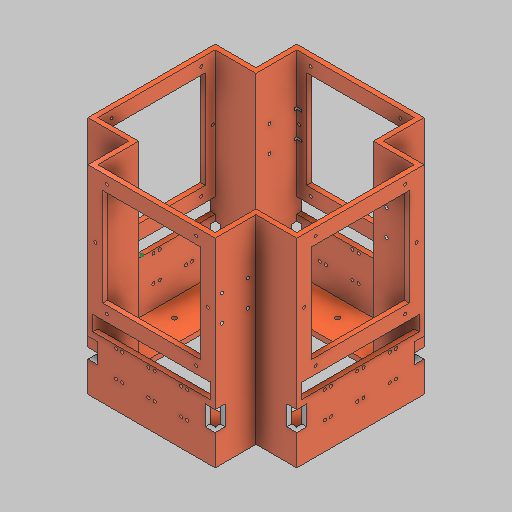
# Autodesk Inventor part: Armadura Interna
Saved by Autodesk Inventor 2027 (Build 310192000, 192)
## iProperties
Created: 2026-11-23
Part Number: Armadura Interna
Material: Genérico
Document SubType Name: Modeling
Designer: Alexander
Density: 1 g/cm^3
Appearance: Valor por defecto
Author: Alexander
Autodesk Inventor part; units mm, degrees
ref_plane "YZ Plane" through (0, 0, 0) normal (1, 0, 0) x (0, 1, 0)
ref_plane "XZ Plane" through (0, 0, 0) normal (0, 1, 0) x (-1, 0, 0)
ref_plane "XY Plane" through (0, 0, 0) normal (0, 0, 1) x (1, 0, 0)
sketch "Boceto1" plane through (0, 0, 0) normal (0, 0, 1) x (1, 0, 0)
  line L0 (-35.2785, 43.9297) -> (54.7215, 43.9297)
  line L1 (54.7215, 43.9297) -> (54.7215, -69.0703)
  line L2 (54.7215, -69.0703) -> (-35.2785, -69.0703)
  line L3 (-35.2785, -69.0703) -> (-35.2785, 43.9297)
  circle A0 centre (-35.2785, 43.9297) radius 1.5
  circle A1 centre (54.7215, 43.9297) radius 1.5
  circle A2 centre (54.7215, -69.0703) radius 1.5
  circle A3 centre (-35.2785, -69.0703) radius 1.5
  line L4 (-54.2785, 51.4297) -> (73.7215, 51.4297)
  line L5 (73.7215, 51.4297) -> (73.7215, -76.5703)
  line L6 (73.7215, -76.5703) -> (-54.2785, -76.5703)
  line L7 (-54.2785, -76.5703) -> (-54.2785, 51.4297)
  line L8 (-54.2785, -12.5703) -> (73.7215, -12.5703)
  circle A4 centre (-46.7785, -12.5703) radius 1.5
  circle A5 centre (66.2215, -12.5703) radius 1.5
  line L9 (-39.2785, 36.4297) -> (58.7215, 36.4297)
  line L10 (58.7215, 36.4297) -> (58.7215, -61.5703)
  line L11 (58.7215, -61.5703) -> (-39.2785, -61.5703)
  line L12 (-39.2785, -61.5703) -> (-39.2785, 36.4297)
  line L13 (-54.2785, 51.4297) -> (73.7215, 51.4297)
  line L14 (73.7215, 51.4297) -> (73.7215, -148.5703)
  line L15 (73.7215, -148.5703) -> (-54.2785, -148.5703)
  line L16 (-54.2785, -148.5703) -> (-54.2785, 51.4297)
  line L17 (-39.2785, -61.5703) -> (-54.2785, -61.5703)
  line L18 (-54.2785, -61.5703) -> (-54.2785, -148.5703)
  line L19 (-54.2785, -148.5703) -> (-39.2785, -148.5703)
  line L20 (-39.2785, -148.5703) -> (-39.2785, -61.5703)
  line L21 (58.7215, -61.5703) -> (73.7215, -61.5703)
  line L22 (73.7215, -61.5703) -> (73.7215, -148.5703)
  line L23 (73.7215, -148.5703) -> (58.7215, -148.5703)
  line L24 (58.7215, -148.5703) -> (58.7215, -61.5703)
  line L25 (-54.2785, -148.5703) -> (73.7215, -148.5703)
  line L26 (73.7215, -148.5703) -> (73.7215, -143.5703)
  line L27 (73.7215, -143.5703) -> (-54.2785, -143.5703)
  line L28 (-54.2785, -143.5703) -> (-54.2785, -148.5703)
  point P0 (0, 0)
  point P1 (-39.2785, -61.5703)
  point P2 (-39.2785, -143.5703)
  point P3 (-39.2785, -76.5703)
  point P4 (58.7215, -76.5703)
  point P5 (58.7215, -143.5703)
  point P6 (-54.2785, -76.5703)
  dimension "d0" = 90
  dimension "d1" = 113
  dimension "d2" = 3
  dimension "d3" = 3
  dimension "d4" = 3
  dimension "d5" = 3
  dimension "d6" = 128
  dimension "d7" = 128
  dimension "d8" = 7.5
  dimension "d9" = 19
  dimension "d10" = 3
  dimension "d11" = 3
  dimension "d12" = 7.5
  dimension "d13" = 7.5
  dimension "d14" = 15
  dimension "d15" = 15
  dimension "d16" = 15
  dimension "d17" = 15
  dimension "d18" = 15
  dimension "d19" = 15
  dimension "d20" = 15
  dimension "d21" = 15
  dimension "d22" = 200
  dimension "d23" = 5
  constraints: 58 end point, 14 parallel, 7 horizontal, 7 perpendicular, 6 centre point, 4 coincident, 3 point on line, 2 midpoint
  measures "d0" distance of L0.start L0.end
  measures "d1" distance of L2.end L0.start
  measures "d2" diameter of A0
  measures "d3" diameter of A1
  measures "d4" diameter of A2
  measures "d5" diameter of A3
  measures "d6" distance of L4.start L4.end
  measures "d7" distance of L6.end L4.start
  measures "d8" distance from line of L4 A0.centre
  measures "d9" distance from line of L7 A0.centre
  measures "d10" diameter of A4
  measures "d11" diameter of A5
  measures "d12" distance from line of L5 A5.centre
  measures "d13" distance from line of L7 A4.centre
  measures "d14" distance from line of L5 L10.end
  measures "d15" distance from line of L10.end L6
  measures "d16" distance from line of point (58.722, 36.43) L4
  measures "d17" distance from line of point (58.722, 36.43) L5
  measures "d18" distance from line of L7 L9.start
  measures "d19" distance from line of L9.start L4
  measures "d20" distance from line of L7 point (-39.278, -61.57)
  measures "d21" distance from line of point (-39.278, -61.57) L6
  measures "d22" distance between parallel lines of L15 L13
  measures "d23" distance between parallel lines of L27 L15
extrude "Extrusión1" add sketch "Boceto1" along normal blind 5 contours A0 L3 L9 L12 L8 A4 L7 L4 L5 A5 L10 L1 A1 L0 | L0 A1 L1 L9 L3 A0 | L11 L1 A2 L2 A3 L3 | L3 A3 L2 A2 L1 L11 L24 L6 L20 | L12 L17 L7 L8 A4 | L20 L6 L7 L17 | L8 A5 L5 L21 L10 | L21 L5 L6 L24 | L20 L27 L16 L6 | L6 L14 L27 L24 | L27 L24 L15 L20 | L20 L15 L16 L27 | L27 L14 L15 L24
extrude "Extrusión2" add sketch "Boceto1" along normal blind 40 contours L27 L24 L15 L20
extrude "Extrusión3" add sketch "Boceto1" along normal blind 41 contours L27 L24 L15 L20 | L20 L15 L16 L27 | L27 L14 L15 L24
sketch "Boceto2" plane through (-54.2785, 51.4297, 0) normal (0, 1, 0) x (1, 0, 0)
  line L0 (0, 0) -> (0, -41) projected
  line L1 (0, 0) -> (128, 0)
  line L2 (128, 0) -> (128, -210)
  line L3 (128, -210) -> (0, -210)
  line L4 (0, -210) -> (0, 0)
  line L5 (0, -169) -> (128, -169)
  line L6 (128, -169) -> (128, -41)
  line L7 (128, -41) -> (0, -41)
  line L8 (0, -41) -> (0, -169)
  line L9 (169, -41) -> (-41, -41)
  line L10 (-41, -41) -> (-41, -169)
  line L11 (-41, -169) -> (169, -169)
  line L12 (169, -169) -> (169, -41)
  line L13 (0, 0) -> (5, 0)
  line L14 (5, 0) -> (5, -210)
  line L15 (5, -210) -> (0, -210)
  line L16 (0, -210) -> (0, 0)
  line L17 (128, 0) -> (123, 0)
  line L18 (123, 0) -> (123, -210)
  line L19 (123, -210) -> (128, -210)
  line L20 (128, -210) -> (128, 0)
  line L21 (-41, -41) -> (169, -41)
  line L22 (169, -41) -> (169, -46)
  line L23 (169, -46) -> (-41, -46)
  line L24 (-41, -46) -> (-41, -41)
  line L25 (169, -169) -> (-41, -169)
  line L26 (-41, -169) -> (-41, -164)
  line L27 (-41, -164) -> (169, -164)
  line L28 (169, -164) -> (169, -169)
  line L29 (169, -41) -> (164, -41)
  line L30 (164, -41) -> (164, -169)
  line L31 (164, -169) -> (169, -169)
  line L32 (169, -169) -> (169, -41)
  line L33 (-41, -41) -> (-36, -41)
  line L34 (-36, -41) -> (-36, -169)
  line L35 (-36, -169) -> (-41, -169)
  line L36 (-41, -169) -> (-41, -41)
  line L37 (0, -210) -> (128, -210)
  line L38 (128, -210) -> (128, -205)
  line L39 (128, -205) -> (0, -205)
  line L40 (0, -205) -> (0, -210)
  point P0 (54.2785, 0)
  point P1 (164, -164)
  point P2 (123, -164)
  point P3 (123, -205)
  point P4 (5, -205)
  point P5 (5, -164)
  point P6 (-36, -164)
  point P7 (-36, -46)
  point P8 (5, -46)
  point P9 (0, -169)
  point P10 (123, -46)
  point P11 (164, -46)
  dimension "d34" = 128
  dimension "d35" = 210
  dimension "d36" = 128
  dimension "d37" = 41
  dimension "d38" = 41
  dimension "d39" = 41
  dimension "d40" = 5
  dimension "d41" = 5
  dimension "d42" = 5
  dimension "d43" = 5
  dimension "d44" = 5
  dimension "d45" = 5
  dimension "d46" = 5
  constraints: 80 end point, 20 parallel, 10 horizontal, 10 perpendicular, 10 point on line
  measures "d34" distance of L2.end L3.end
  measures "d35" distance of L1.end L2.end
  measures "d36" distance of L6.end L5.end
  measures "d37" distance between parallel lines of L5 L3
  measures "d38" distance between parallel lines of L4 L10
  measures "d39" distance between parallel lines of L12 L2
  measures "d40" distance of L14.end L15.end
  measures "d41" distance of L19.end L18.end
  measures "d42" distance of L21.end L22.end
  measures "d43" distance of L25.end L26.end
  measures "d44" distance of L31.end L30.end
  measures "d45" distance of L34.end L35.end
  measures "d46" distance of L38.end L37.end
extrude "Extrusión4" add sketch "Boceto2" against normal blind 200 contours L1 L14 L7 L0 | L7 L14 L23 L4 | L4 L23 L34 L9 | L34 L23 L10 L9 | L1 L2 L7 L18 | L27 L14 L5 L4 | L4 L11 L34 L27 | L34 L27 L10 L23 | L7 L2 L23 L18 | L5 L14 L39 L4 | L34 L11 L10 L27 | L9 L30 L23 L2 | L39 L14 L3 L4 | L27 L2 L5 L18 | L9 L12 L23 L30 | L39 L18 L3 L14 | L5 L2 L39 L18 | L27 L30 L11 L2 | L23 L12 L27 L30 | L39 L2 L3 L18 | L27 L12 L11 L30
sketch "Boceto4" plane through (68.7215, 51.4297, 205) normal (0, 0, -1) x (-1, 0, 0)
  line L0 (10, -15) -> (10, -113) projected
  line L1 (10, -15) -> (108, -15)
  line L2 (108, -15) -> (108, -113)
  line L3 (108, -113) -> (10, -113)
  line L4 (10, -113) -> (10, -15)
  line L5 (108, -128) -> (10, -128) projected
  line L6 (10, -195) -> (108, -195) projected
  line L7 (10, -128) -> (108, -128)
  line L8 (108, -128) -> (108, -195)
  line L9 (108, -195) -> (10, -195)
  line L10 (10, -195) -> (10, -128)
  circle A0 centre (14, -120.5) radius 1.5 projected
  circle A1 centre (14, -120.5) radius 1.5
  circle A2 centre (104, -120.5) radius 1.5 projected
  circle A3 centre (104, -120.5) radius 1.5
  circle A4 centre (115.5, -64) radius 1.5 projected
  circle A5 centre (115.5, -64) radius 1.5
  circle A6 centre (104, -7.5) radius 1.5 projected
  circle A7 centre (104, -7.5) radius 1.5
  circle A8 centre (14, -7.5) radius 1.5 projected
  circle A9 centre (14, -7.5) radius 1.5
  circle A10 centre (2.5, -64) radius 1.5 projected
  circle A11 centre (2.5, -64) radius 1.5
  point P0 (68.7215, -51.4297)
  point P1 (10, -113)
  constraints: 16 end point, 6 centre point, 6 coincident, 4 parallel, 2 horizontal, 2 perpendicular
extrude "Extrusión5" cut sketch "Boceto4" against normal blind 200
sketch "Boceto5" plane through (-95.2785, 51.4297, 41) normal (-1, 0, 0) x (0, 0, 1)
  line L0 (15, -15) -> (113, -15)
  line L1 (113, -15) -> (113, -113)
  line L2 (113, -113) -> (15, -113)
  line L3 (15, -113) -> (15, -15)
  line L4 (0, 0) -> (128, 0) projected
  line L5 (0, 0) -> (0, -200) projected
  line L6 (15, -128) -> (113, -128)
  line L7 (113, -128) -> (113, -195)
  line L8 (113, -195) -> (15, -195)
  line L9 (15, -195) -> (15, -128)
  line L10 (128, -200) -> (0, -200) projected
  point P0 (-41, -51.4297)
  dimension "d51" = 98
  dimension "d52" = 98
  dimension "d53" = 15
  dimension "d54" = 15
  dimension "d55" = 5
  dimension "d56" = 15
  constraints: 16 end point, 4 parallel, 2 horizontal, 2 perpendicular
  measures "d51" distance of L1.end L2.end
  measures "d52" distance of L0.end L1.end
  measures "d53" distance between parallel lines of L4 L0
  measures "d54" distance between parallel lines of L5 L3
  measures "d55" distance between parallel lines of L10 L8
  measures "d56" distance between parallel lines of L6 L2
extrude "Extrusión6" cut sketch "Boceto5" against normal blind 243.75
sketch "Boceto6" plane through (-95.2785, 51.4297, 41) normal (-1, 0, 0) x (0, 0, 1)
  circle A0 centre (19, -7.5) radius 1.5
  circle A1 centre (109, -7.5) radius 1.5
  circle A2 centre (19, -120.5) radius 1.5
  circle A3 centre (109, -120.5) radius 1.5
  line L0 (0, 0) -> (128, 0) projected
  line L1 (113, -113) -> (15, -113) projected
  line L2 (128, 0) -> (128, -200) projected
  line L3 (15, -113) -> (15, -15) projected
  line L4 (15, -64) -> (0, -64)
  line L5 (0, 0) -> (0, -200) projected
  line L6 (113, -15) -> (113, -113) projected
  line L7 (113, -64) -> (128, -64)
  circle A4 centre (7.5, -64) radius 1.5
  circle A5 centre (120.5, -64) radius 1.5
  point P0 (-41, -51.4297)
  dimension "d59" = 3
  dimension "d60" = 3
  dimension "d61" = 90
  dimension "d62" = 3
  dimension "d63" = 3
  dimension "d64" = 7.5
  dimension "d65" = 7.5
  dimension "d67" = 7.5
  dimension "d69" = 7.5
  dimension "d70" = 19
  dimension "d71" = 19
  dimension "d72" = 90
  dimension "d73" = 3
  dimension "d74" = 3
  constraints: 6 centre point, 4 end point, 4 midpoint, 3 point on line, 1 horizontal
  measures "d59" diameter of A0
  measures "d60" diameter of A1
  measures "d61" distance of A0.centre A1.centre
  measures "d62" diameter of A2
  measures "d63" diameter of A3
  measures "d64" distance from line of L0 A0.centre
  measures "d65" distance from line of A1.centre L0
  measures "d67" distance from line of L1 A2.centre
  measures "d69" distance from line of L1 A3.centre
  measures "d70" distance from line of L2 A1.centre
  measures "d71" distance from line of L2 A3.centre
  measures "d72" distance of A2.centre A3.centre
  measures "d73" diameter of A4
  measures "d74" diameter of A5
extrude "Extrusión7" cut sketch "Boceto6" against normal blind 243.75 contours A0 | A1 | A2 | A3 | A4 L4 | L4 A4 | A5 L7 | L7 A5
sketch "Boceto7" plane through (-54.2785, -148.5703, 0) normal (0, -1, 0) x (1, 0, 0)
  line L0 (123, 164) -> (123, 205) projected
  line L1 (169, 41) -> (128, 41) projected
  line L2 (123, 164) -> (169, 164)
  line L3 (169, 164) -> (169, 41)
  line L4 (169, 41) -> (123, 41)
  line L5 (123, 41) -> (123, 164)
  line L6 (0, 210) -> (0, 169) projected
  line L7 (123, 164) -> (0, 164)
  line L8 (0, 164) -> (0, 210)
  line L9 (0, 210) -> (123, 210)
  line L10 (123, 210) -> (123, 164)
  line L11 (-41, 169) -> (-41, 41) projected
  line L12 (5, 164) -> (5, 205) projected
  line L13 (-41, 41) -> (5, 41)
  line L14 (5, 41) -> (5, 164)
  line L15 (5, 164) -> (-41, 164)
  line L16 (-41, 164) -> (-41, 41)
  line L17 (-36, 46) -> (5, 46) projected
  line L18 (123, 41) -> (-36, 41)
  line L19 (-36, 41) -> (-36, 46)
  line L20 (-36, 46) -> (123, 46)
  line L21 (123, 46) -> (123, 41)
  point P0 (54.2785, 0)
  point P1 (0, 164)
  point P2 (-36, 41)
  constraints: 32 end point, 8 parallel, 4 horizontal, 4 perpendicular
extrude "Extrusión8" add sketch "Boceto7" against normal blind 5 contours L7 L8 L6 L9 L10 L0 | L2 L3 L1 L4 L5 | L5 L18 L14 L20 | L14 L17 L19 L13 L11 L15 L7
sketch "Boceto8" plane through (109.7215, -143.5703, 56) normal (0, 1, 0) x (1, 0, 0)
  line L0 (5, 0) -> (5, -98) projected
  line L1 (5, -49) -> (-205, -49)
  line L2 (-205, 0) -> (-205, -98) projected
  line L3 (-51, -154) -> (-149, -154) projected
  line L4 (-100, -154) -> (-100, 56)
  line L5 (-51, 56) -> (-149, 56) projected
  line L6 (-41, -108) -> (-41, 10) projected
  line L7 (-41, -49) -> (5, -49)
  line L8 (-41, -108) -> (-159, -108) projected
  line L9 (-100, -108) -> (-100, -154)
  line L10 (-149, -149) -> (-51, -149) projected
  line L11 (-205, -49) -> (-159, -49)
  line L12 (-159, -108) -> (-159, 10) projected
  line L13 (-100, 56) -> (-100, 10)
  line L14 (-41, 10) -> (-159, 10) projected
  circle A0 centre (-100, -131) radius 2.5
  circle A1 centre (-18, -49) radius 2.5
  circle A2 centre (-100, 33) radius 2.5
  circle A3 centre (-182, -49) radius 2.5
  point P0 (-109.7215, 56)
  dimension "d79" = 5
  dimension "d80" = 5
  dimension "d81" = 5
  dimension "d82" = 5
  constraints: 12 end point, 12 midpoint, 4 centre point, 2 perpendicular
  measures "d79" diameter of A0
  measures "d80" diameter of A1
  measures "d81" diameter of A2
  measures "d82" diameter of A3
extrude "Extrusión9" cut sketch "Boceto8" against normal blind 5 contours A3 L1 | L1 A3 | A2 L4 | L4 A2 | A1 L1 | L1 A1 | A0 L4 | L4 A0
sketch "Boceto9" plane through (-54.2785, 51.4297, 210) normal (0, 0, 1) x (1, 0, 0)
  line L0 (5, 0) -> (5, -195) projected
  line L1 (113, -195) -> (123, -195) projected
  line L2 (5, -127.8283) -> (123, -127.8283)
  line L3 (123, -127.8283) -> (123, -195)
  line L4 (123, -195) -> (5, -195)
  line L5 (5, -195) -> (5, -127.8283)
  point P0 (54.2785, -51.4297)
  constraints: 8 end point, 2 parallel, 1 horizontal, 1 perpendicular, 1 point on line
extrude "Extrusión10" cut sketch "Boceto9" against normal blind 306.75
sketch "Boceto10" plane through (114.7215, 51.4297, 169) normal (1, 0, 0) x (0, 0, -1)
  line L0 (5, -195) -> (123, -195) projected
  line L1 (5, 0) -> (5, -195) projected
  line L2 (123, -195) -> (5, -195)
  line L3 (5, -195) -> (5, -127.9827)
  line L4 (5, -127.9827) -> (123, -127.9827)
  line L5 (123, -127.9827) -> (123, -195)
  point P0 (169, -51.4297)
  constraints: 8 end point, 2 parallel, 1 horizontal, 1 perpendicular, 1 point on line
extrude "Extrusión11" cut sketch "Boceto10" against normal blind 306.75
sketch "Boceto11" plane through (114.7215, 51.4297, 169) normal (1, 0, 0) x (0, 0, -1)
  line L0 (-2.5, -143) -> (130.5, -143)
  line L1 (130.5, -143) -> (130.5, -176)
  line L2 (130.5, -176) -> (-2.5, -176)
  line L3 (-2.5, -176) -> (-2.5, -143)
  line L4 (128, -200) -> (0, -200) projected
  line L5 (64, -200) -> (64, -113)
  line L6 (15, -113) -> (113, -113) projected
  line L7 (1.7375, -146) -> (28.2375, -146)
  line L8 (28.2375, -146) -> (28.2375, -172.5)
  line L9 (28.2375, -172.5) -> (1.7375, -172.5)
  line L10 (1.7375, -172.5) -> (1.7375, -146)
  line L11 (28.2375, -146) -> (34.4125, -146)
  line L12 (34.4125, -146) -> (34.4125, -172.5)
  line L13 (34.4125, -172.5) -> (28.2375, -172.5)
  line L14 (28.2375, -172.5) -> (28.2375, -146)
  line L15 (34.4125, -146) -> (60.9125, -146)
  line L16 (60.9125, -146) -> (60.9125, -172.5)
  line L17 (60.9125, -172.5) -> (34.4125, -172.5)
  line L18 (34.4125, -172.5) -> (34.4125, -146)
  line L19 (60.9125, -146) -> (67.0875, -146)
  line L20 (67.0875, -146) -> (67.0875, -172.5)
  line L21 (67.0875, -172.5) -> (60.9125, -172.5)
  line L22 (60.9125, -172.5) -> (60.9125, -146)
  line L23 (67.0875, -146) -> (93.5875, -146)
  line L24 (93.5875, -146) -> (93.5875, -172.5)
  line L25 (93.5875, -172.5) -> (67.0875, -172.5)
  line L26 (67.0875, -172.5) -> (67.0875, -146)
  line L27 (93.5875, -172.5) -> (99.7625, -172.5)
  line L28 (99.7625, -172.5) -> (99.7625, -146)
  line L29 (99.7625, -146) -> (93.5875, -146)
  line L30 (93.5875, -146) -> (93.5875, -172.5)
  line L31 (99.7625, -146) -> (126.2625, -146)
  line L32 (126.2625, -146) -> (126.2625, -172.5)
  line L33 (126.2625, -172.5) -> (99.7625, -172.5)
  line L34 (99.7625, -172.5) -> (99.7625, -146)
  circle A0 centre (1.7375, -146) radius 1.6
  circle A1 centre (28.2375, -146) radius 1.6
  circle A2 centre (60.9125, -146) radius 1.6
  circle A3 centre (67.0875, -146) radius 1.6
  circle A4 centre (34.4125, -146) radius 1.6
  circle A5 centre (93.5875, -146) radius 1.6
  circle A6 centre (99.7625, -146) radius 1.6
  circle A7 centre (126.2625, -146) radius 1.6
  circle A8 centre (1.7375, -172.5) radius 1.6
  circle A9 centre (28.2375, -172.5) radius 1.6
  circle A10 centre (34.4125, -172.5) radius 1.6
  circle A11 centre (60.9125, -172.5) radius 1.6
  circle A12 centre (67.0875, -172.5) radius 1.6
  circle A13 centre (93.5875, -172.5) radius 1.6
  circle A14 centre (99.7625, -172.5) radius 1.6
  circle A15 centre (126.2625, -172.5) radius 1.6
  line L35 (128, -200) -> (128, 0) projected
  line L36 (0, -200) -> (128, -200)
  line L37 (128, -200) -> (128, -113)
  line L38 (128, -113) -> (0, -113)
  line L39 (0, -113) -> (0, -200)
  point P0 (169, -51.4297)
  point P1 (0, -143)
  point P2 (128, -143)
  dimension "d89" = 133
  dimension "d90" = 66.5
  dimension "d91" = 30
  dimension "d92" = 33
  dimension "d93" = 26.5
  dimension "d94" = 26.5
  dimension "d95" = 6.175
  dimension "d96" = 26.5
  dimension "d97" = 6.175
  dimension "d98" = 26.5
  dimension "d99" = 6.175
  dimension "d100" = 26.5
  dimension "d101" = 4.2375
  dimension "d102" = 3
  dimension "d103" = 4.2375
  dimension "d104" = 3.2
  dimension "d105" = 3.2
  dimension "d106" = 3.2
  dimension "d107" = 3.2
  dimension "d108" = 3.2
  dimension "d109" = 3.2
  dimension "d110" = 3.2
  dimension "d111" = 3.2
  dimension "d112" = 3.2
  dimension "d113" = 3.2
  dimension "d114" = 3.2
  dimension "d115" = 3.2
  dimension "d116" = 3.2
  dimension "d117" = 3.2
  dimension "d118" = 3.2
  dimension "d119" = 3.2
  dimension "d120" = 24
  constraints: 74 end point, 18 parallel, 16 centre point, 16 coincident, 9 horizontal, 9 perpendicular, 4 point on line, 2 midpoint
  measures "d89" distance of L1.end L2.end
  measures "d90" distance between parallel lines of L5 L1
  measures "d91" distance between parallel lines of L0 L6
  measures "d92" distance between parallel lines of L2 L0
  measures "d93" distance of L8.end L9.end
  measures "d94" distance of L7.end L8.end
  measures "d95" distance of L12.end L13.end
  measures "d96" distance of L16.end L17.end
  measures "d97" distance of L20.end L21.end
  measures "d98" distance of L24.end L25.end
  measures "d99" distance of L29.end L28.end
  measures "d100" distance of L32.end L33.end
  measures "d101" distance between parallel lines of L3 L10
  measures "d102" distance between parallel lines of L0 L7
  measures "d103" distance between parallel lines of L32 L1
  measures "d104" diameter of A0
  measures "d105" diameter of A1
  measures "d106" diameter of A2
  measures "d107" diameter of A3
  measures "d108" diameter of A4
  measures "d109" diameter of A5
  measures "d110" diameter of A6
  measures "d111" diameter of A7
  measures "d112" diameter of A8
  measures "d113" diameter of A9
  measures "d114" diameter of A10
  measures "d115" diameter of A11
  measures "d116" diameter of A12
  measures "d117" diameter of A13
  measures "d118" diameter of A14
  measures "d119" diameter of A15
  measures "d120" distance between parallel lines of L4 L2
sketch "Boceto12" plane through (-54.2785, 51.4297, 210) normal (0, 0, 1) x (1, 0, 0)
  point P0 (54.2785, -51.4297)
sketch "Boceto13" plane through (-54.2785, 51.4297, 210) normal (0, 0, 1) x (1, 0, 0)
  line L0 (-2.502, -142.9987) -> (130.498, -142.9987)
  line L1 (130.498, -142.9987) -> (130.498, -175.9987)
  line L2 (130.498, -175.9987) -> (-2.502, -175.9987)
  line L3 (-2.502, -175.9987) -> (-2.502, -142.9987)
  line L4 (127.998, -199.9987) -> (-0.002, -199.9987)
  line L5 (63.998, -199.9987) -> (63.998, -112.9987)
  line L6 (14.998, -112.9987) -> (112.998, -112.9987)
  line L7 (1.7355, -145.9987) -> (28.2355, -145.9987)
  line L8 (28.2355, -145.9987) -> (28.2355, -172.4987)
  line L9 (28.2355, -172.4987) -> (1.7355, -172.4987)
  line L10 (1.7355, -172.4987) -> (1.7355, -145.9987)
  line L11 (28.2355, -145.9987) -> (34.4105, -145.9987)
  line L12 (34.4105, -145.9987) -> (34.4105, -172.4987)
  line L13 (34.4105, -172.4987) -> (28.2355, -172.4987)
  line L14 (28.2355, -172.4987) -> (28.2355, -145.9987)
  line L15 (34.4105, -145.9987) -> (60.9105, -145.9987)
  line L16 (60.9105, -145.9987) -> (60.9105, -172.4987)
  line L17 (60.9105, -172.4987) -> (34.4105, -172.4987)
  line L18 (34.4105, -172.4987) -> (34.4105, -145.9987)
  line L19 (60.9105, -145.9987) -> (67.0855, -145.9987)
  line L20 (67.0855, -145.9987) -> (67.0855, -172.4987)
  line L21 (67.0855, -172.4987) -> (60.9105, -172.4987)
  line L22 (60.9105, -172.4987) -> (60.9105, -145.9987)
  line L23 (67.0855, -145.9987) -> (93.5855, -145.9987)
  line L24 (93.5855, -145.9987) -> (93.5855, -172.4987)
  line L25 (93.5855, -172.4987) -> (67.0855, -172.4987)
  line L26 (67.0855, -172.4987) -> (67.0855, -145.9987)
  line L27 (93.5855, -172.4987) -> (99.7605, -172.4987)
  line L28 (99.7605, -172.4987) -> (99.7605, -145.9987)
  line L29 (99.7605, -145.9987) -> (93.5855, -145.9987)
  line L30 (93.5855, -145.9987) -> (93.5855, -172.4987)
  line L31 (99.7605, -145.9987) -> (126.2605, -145.9987)
  line L32 (126.2605, -145.9987) -> (126.2605, -172.4987)
  line L33 (126.2605, -172.4987) -> (99.7605, -172.4987)
  line L34 (99.7605, -172.4987) -> (99.7605, -145.9987)
  circle A0 centre (1.7355, -145.9987) radius 1.6
  circle A1 centre (28.2355, -145.9987) radius 1.6
  circle A2 centre (60.9105, -145.9987) radius 1.6
  circle A3 centre (67.0855, -145.9987) radius 1.6
  circle A4 centre (34.4105, -145.9987) radius 1.6
  circle A5 centre (93.5855, -145.9987) radius 1.6
  circle A6 centre (99.7605, -145.9987) radius 1.6
  circle A7 centre (126.2605, -145.9987) radius 1.6
  circle A8 centre (1.7355, -172.4987) radius 1.6
  circle A9 centre (28.2355, -172.4987) radius 1.6
  circle A10 centre (34.4105, -172.4987) radius 1.6
  circle A11 centre (60.9105, -172.4987) radius 1.6
  circle A12 centre (67.0855, -172.4987) radius 1.6
  circle A13 centre (93.5855, -172.4987) radius 1.6
  circle A14 centre (99.7605, -172.4987) radius 1.6
  circle A15 centre (126.2605, -172.4987) radius 1.6
  line L35 (-0.002, -199.9987) -> (127.998, -199.9987)
  line L36 (127.998, -199.9987) -> (127.998, -112.9987)
  line L37 (127.998, -112.9987) -> (-0.002, -112.9987)
  line L38 (-0.002, -112.9987) -> (-0.002, -199.9987)
  line L39 (5, -127.8283) -> (5, -195) projected
  line L40 (169, -195) -> (123, -195) projected
  line L41 (5, -142.9987) -> (123, -142.9987)
  line L42 (123, -142.9987) -> (123, -195)
  line L43 (123, -195) -> (5, -195)
  line L44 (5, -195) -> (5, -142.9987)
  point P0 (54.2785, -51.4297)
  dimension "d121" = 133
  dimension "d122" = 66.5
  dimension "d123" = 30
  dimension "d124" = 33
  dimension "d125" = 26.5
  dimension "d126" = 26.5
  dimension "d127" = 6.175
  dimension "d128" = 26.5
  dimension "d129" = 6.175
  dimension "d130" = 26.5
  dimension "d131" = 6.175
  dimension "d132" = 26.5
  dimension "d133" = 4.2375
  dimension "d134" = 3
  dimension "d135" = 4.2375
  dimension "d136" = 3.2
  dimension "d137" = 3.2
  dimension "d138" = 3.2
  dimension "d139" = 3.2
  dimension "d140" = 3.2
  dimension "d141" = 3.2
  dimension "d142" = 3.2
  dimension "d143" = 3.2
  dimension "d144" = 3.2
  dimension "d145" = 3.2
  dimension "d146" = 3.2
  dimension "d147" = 3.2
  dimension "d148" = 3.2
  dimension "d149" = 3.2
  dimension "d150" = 3.2
  dimension "d151" = 3.2
  dimension "d152" = 24
  constraints: 86 end point, 20 parallel, 16 centre point, 16 coincident, 10 horizontal, 10 perpendicular, 5 point on line, 2 midpoint
  measures "d121" distance of L1.end L2.end
  measures "d122" distance between parallel lines of L5 L1
  measures "d123" distance between parallel lines of L0 L6
  measures "d124" distance between parallel lines of L2 L0
  measures "d125" distance of L9.start L9.end
  measures "d126" distance of L11.start L9.start
  measures "d127" distance of L13.start L13.end
  measures "d128" distance of L16.end L17.end
  measures "d129" distance of L20.end L21.end
  measures "d130" distance of L25.start L25.end
  measures "d131" distance of L30.start L29.start
  measures "d132" distance of L33.start L33.end
  measures "d133" distance between parallel lines of L3 L10
  measures "d134" distance between parallel lines of L0 L7
  measures "d135" distance between parallel lines of L32 L1
  measures "d136" diameter of A0
  measures "d137" diameter of A1
  measures "d138" diameter of A2
  measures "d139" diameter of A3
  measures "d140" diameter of A4
  measures "d141" diameter of A5
  measures "d142" diameter of A6
  measures "d143" diameter of A7
  measures "d144" diameter of A8
  measures "d145" diameter of A9
  measures "d146" diameter of A10
  measures "d147" diameter of A11
  measures "d148" diameter of A12
  measures "d149" diameter of A13
  measures "d150" diameter of A14
  measures "d151" diameter of A15
  measures "d152" distance between parallel lines of L4 L2
extrude "Extrusión12" add sketch "Boceto13" against normal blind 5 contours L0 L5 L19 A2 L15 A4 L11 A1 L7 L39 | L0 L42 L31 A6 L29 A5 L23 A3 L19 L5 | L7 A1 L8 A9 L9 L39 | L39 L9 A9 L13 A10 L17 A11 L21 L5 L2 | L2 L5 L43 L39 | L19 A3 L20 A12 L21 L5 | L5 L21 A11 L16 A2 L19 | L5 L21 A12 L25 A13 L27 A14 L33 L42 L2 | L2 L42 L43 L5 | L42 L33 A14 L28 A6 L31 | L11 A4 L12 A10 L13 A9 L8 A1 | A2 L16 A11 L17 A10 L12 A4 L15 | L23 A5 L24 A13 L25 A12 L20 A3 | A6 L28 A14 L27 A13 L24 A5 L29
extrude "Extrusión13" add sketch "Boceto11" against normal blind 5 contours L0 L5 L19 A2 L15 A4 L11 A1 L7 A0 L10 A8 L9 A9 L13 A10 L17 A11 L21 L2 L39 | L0 L35 L2 L5 L21 A12 L25 A13 L27 A14 L33 A15 L32 A7 L31 A6 L29 A5 L23 A3 L19 | L2 L5 L4 L39 | L19 A3 L20 A12 L21 L5 | L5 L21 A11 L16 A2 L19 | L2 L35 L4 L5 | A2 L16 A11 L17 A10 L12 A4 L15 | L23 A5 L24 A13 L25 A12 L20 A3 | A4 L12 A10 L13 A9 L8 A1 L11 | L29 A6 L28 A14 L27 A13 L24 A5 | A1 L8 A9 L9 A8 L10 A0 L7 | L31 A7 L32 A15 L33 A14 L28 A6
sketch "Boceto14" plane through (0, 0, 0) normal (0, 0, -1) x (-1, 0, 0)
  line L0 (49.2785, -91.569) -> (-68.7215, -91.569) projected
  line L1 (49.2785, 51.4297) -> (49.2785, -143.5703) projected
  line L2 (-68.7215, -91.569) -> (49.2785, -91.569)
  line L3 (49.2785, -91.569) -> (49.2785, -143.5703)
  line L4 (49.2785, -143.5703) -> (-68.7215, -143.5703)
  line L5 (-68.7215, -143.5703) -> (-68.7215, -91.569)
  circle A0 centre (-45.482, -94.569) radius 1.6 projected
  circle A1 centre (-45.482, -94.569) radius 1.6
  circle A2 centre (-39.307, -94.569) radius 1.6 projected
  circle A3 centre (-39.307, -94.569) radius 1.6
  circle A4 centre (-45.482, -121.069) radius 1.6 projected
  circle A5 centre (-45.482, -121.069) radius 1.6
  circle A6 centre (-39.307, -121.069) radius 1.6 projected
  circle A7 centre (-39.307, -121.069) radius 1.6
  circle A8 centre (-12.807, -94.569) radius 1.6 projected
  circle A9 centre (-12.807, -94.569) radius 1.6
  circle A10 centre (-12.807, -121.069) radius 1.6 projected
  circle A11 centre (-12.807, -121.069) radius 1.6
  circle A12 centre (-6.632, -94.569) radius 1.6 projected
  circle A13 centre (-6.632, -94.569) radius 1.6
  circle A14 centre (19.868, -94.569) radius 1.6 projected
  circle A15 centre (19.868, -94.569) radius 1.6
  circle A16 centre (26.043, -94.569) radius 1.6 projected
  circle A17 centre (26.043, -94.569) radius 1.6
  circle A18 centre (19.868, -121.069) radius 1.6 projected
  circle A19 centre (19.868, -121.069) radius 1.6
  circle A20 centre (26.043, -121.069) radius 1.6 projected
  circle A21 centre (26.043, -121.069) radius 1.6
  circle A22 centre (-6.632, -121.069) radius 1.6 projected
  circle A23 centre (-6.632, -121.069) radius 1.6
  point P0 (0, 0)
  constraints: 12 centre point, 12 coincident, 8 end point, 2 parallel, 1 horizontal, 1 perpendicular
extrude "Extrusión15" add sketch "Boceto14" against normal blind 5
sketch "Boceto15" plane through (-95.2785, 51.4297, 41) normal (-1, 0, 0) x (0, 0, 1)
  line L0 (5, -195) -> (5, -143) projected
  line L1 (123, -195) -> (5, -195) projected
  line L2 (5, -143) -> (123, -143)
  line L3 (123, -143) -> (123, -195)
  line L4 (123, -195) -> (5, -195)
  line L5 (5, -195) -> (5, -143)
  circle A0 centre (28.2375, -146) radius 1.6 projected
  circle A1 centre (28.2375, -146) radius 1.6
  circle A2 centre (34.4125, -146) radius 1.6 projected
  circle A3 centre (34.4125, -146) radius 1.6
  circle A4 centre (28.2375, -172.5) radius 1.6 projected
  circle A5 centre (28.2375, -172.5) radius 1.6
  circle A6 centre (34.4125, -172.5) radius 1.6
  circle A7 centre (60.9125, -172.5) radius 1.6 projected
  circle A8 centre (60.9125, -172.5) radius 1.6
  circle A9 centre (60.9125, -146) radius 1.6 projected
  circle A10 centre (60.9125, -146) radius 1.6
  circle A11 centre (67.0875, -146) radius 1.6 projected
  circle A12 centre (67.0875, -146) radius 1.6
  circle A13 centre (67.0875, -172.5) radius 1.6 projected
  circle A14 centre (67.0875, -172.5) radius 1.6
  circle A15 centre (93.5875, -172.5) radius 1.6 projected
  circle A16 centre (93.5875, -172.5) radius 1.6
  circle A17 centre (99.7625, -172.5) radius 1.6 projected
  circle A18 centre (99.7625, -172.5) radius 1.6
  circle A19 centre (93.5875, -146) radius 1.6 projected
  circle A20 centre (93.5875, -146) radius 1.6
  circle A21 centre (99.7625, -146) radius 1.6 projected
  circle A22 centre (99.7625, -146) radius 1.6
  point P0 (-41, -51.4297)
  constraints: 12 centre point, 11 coincident, 8 end point, 2 parallel, 1 horizontal, 1 perpendicular
extrude "Extrusión16" add sketch "Boceto15" against normal blind 5
sketch "Boceto16" plane through (73.7215, 51.4297, 210) normal (1, 0, 0) x (0, 0, -1)
  circle A0 centre (69.2375, -172.5) radius 1.6 projected
  circle A1 centre (69.2375, -146) radius 1.6 projected
  line L0 (69.2375, -172.5) -> (69.2375, -146)
  line L1 (69.2375, -146) -> (69.2375, -159.25)
  line L2 (69.2375, -159.25) -> (0, -159.25)
  line L3 (0, 0) -> (0, -200) projected
  line L4 (0, -159.25) -> (210, -159.25)
  line L5 (0, -159.25) -> (10, -159.25)
  line L6 (10, -159.25) -> (10, -149.25)
  line L7 (10, -149.25) -> (0, -149.25)
  line L8 (0, -149.25) -> (0, -159.25)
  line L9 (0, -159.25) -> (10, -159.25)
  line L10 (10, -159.25) -> (10, -169.25)
  line L11 (10, -169.25) -> (0, -169.25)
  line L12 (0, -169.25) -> (0, -159.25)
  line L13 (210, -200) -> (210, 0) projected
  line L14 (210, -149.25) -> (200, -149.25)
  line L15 (200, -149.25) -> (200, -169.25)
  line L16 (200, -169.25) -> (210, -169.25)
  line L17 (210, -169.25) -> (210, -149.25)
  point P0 (210, -51.4297)
  point P1 (10, -159.25)
  dimension "d163" = 10
  dimension "d164" = 10
  dimension "d165" = 10
  dimension "d166" = 10
  dimension "d167" = 20
  constraints: 32 end point, 6 parallel, 4 perpendicular, 4 point on line, 3 horizontal, 1 midpoint, 1 vertical
  measures "d163" distance of L7.end L6.end
  measures "d164" distance of L6.end L5.end
  measures "d165" distance of L9.end L10.end
  measures "d166" distance of L16.end L15.end
  measures "d167" distance of L15.end L14.end
extrude "Extrusión17" cut sketch "Boceto16" against normal blind 10 contours L10 L11 L3 L2 | L2 L3 L7 L6 | L15 L14 L13 L4 | L4 L13 L16 L15
sketch "Boceto17" plane through (-54.2785, -148.5703, 0) normal (-1, 0, 0) x (0, 0, 1)
  circle A0 centre (69.2375, 27.5) radius 1.6 projected
  circle A1 centre (69.2375, 54) radius 1.6 projected
  line L0 (69.2375, 27.5) -> (69.2375, 54)
  line L1 (69.2375, 54) -> (69.2375, 40.75)
  line L2 (69.2375, 40.75) -> (0, 40.75)
  line L3 (0, 50.75) -> (0, 30.75) projected
  line L4 (0, 40.75) -> (210, 40.75)
  line L5 (210, 30.75) -> (210, 50.75) projected
  line L6 (5, 50.75) -> (10, 50.75) projected
  line L7 (0, 40.75) -> (10, 40.75)
  line L8 (10, 40.75) -> (10, 50.75)
  line L9 (10, 50.75) -> (0, 50.75)
  line L10 (0, 50.75) -> (0, 40.75)
  line L11 (0, 40.75) -> (10, 40.75)
  line L12 (10, 40.75) -> (10, 30.75)
  line L13 (10, 30.75) -> (0, 30.75)
  line L14 (0, 30.75) -> (0, 40.75)
  line L15 (210, 40.75) -> (200, 40.75)
  line L16 (200, 40.75) -> (200, 50.75)
  line L17 (200, 50.75) -> (210, 50.75)
  line L18 (210, 50.75) -> (210, 40.75)
  line L19 (210, 40.75) -> (200, 40.75)
  line L20 (200, 40.75) -> (200, 30.75)
  line L21 (200, 30.75) -> (210, 30.75)
  line L22 (210, 30.75) -> (210, 40.75)
  point P0 (0, 148.5703)
  dimension "d170" = 10
  dimension "d171" = 10
  dimension "d172" = 10
  dimension "d173" = 10
  dimension "d174" = 10
  constraints: 40 end point, 8 parallel, 4 horizontal, 4 perpendicular, 3 midpoint, 2 point on line, 1 vertical
  measures "d170" distance of L9.end L6.end
  measures "d171" distance of L11.end L12.end
  measures "d172" distance of L16.end L17.end
  measures "d173" distance of L21.end L20.end
  measures "d174" distance of L20.end L19.end
extrude "Extrusión18" cut sketch "Boceto17" against normal blind 10 contours L12 L13 L3 L2 | L2 L3 L9 L6 L8 | L16 L17 L5 L4 | L4 L5 L21 L20
sketch "Boceto18" plane through (-95.2785, 51.4297, 169) normal (0, 0, 1) x (1, 0, 0)
  circle A0 centre (69.2355, -145.9987) radius 1.6 projected
  circle A1 centre (69.2355, -172.4987) radius 1.6 projected
  line L0 (69.2355, -145.9987) -> (69.2355, -172.4987)
  line L1 (69.2355, -172.4987) -> (69.2355, -159.2487)
  line L2 (69.2355, -159.2487) -> (0, -159.2487)
  line L3 (0, 0) -> (0, -200) projected
  line L4 (210, 0) -> (210, -200) projected
  line L5 (210, -159.2487) -> (30.2782, -159.2487)
  line L6 (210, -159.2487) -> (200, -159.2487)
  line L7 (200, -159.2487) -> (200, -169.2487)
  line L8 (200, -169.2487) -> (210, -169.2487)
  line L9 (210, -169.2487) -> (210, -159.2487)
  line L10 (210, -159.2487) -> (200, -159.2487)
  line L11 (200, -159.2487) -> (200, -149.2487)
  line L12 (200, -149.2487) -> (210, -149.2487)
  line L13 (210, -149.2487) -> (210, -159.2487)
  line L14 (0, -159.2487) -> (10, -159.2487)
  line L15 (10, -159.2487) -> (10, -149.2487)
  line L16 (10, -149.2487) -> (0, -149.2487)
  line L17 (0, -149.2487) -> (0, -159.2487)
  line L18 (0, -159.2487) -> (10, -159.2487)
  line L19 (10, -159.2487) -> (10, -169.2487)
  line L20 (10, -169.2487) -> (0, -169.2487)
  line L21 (0, -169.2487) -> (0, -159.2487)
  point P0 (95.2785, -51.4297)
  point P1 (0, -149.2487)
  point P2 (10, -159.2487)
  dimension "d177" = 10
  dimension "d178" = 10
  dimension "d179" = 10
  dimension "d180" = 10
  dimension "d181" = 10
  dimension "d182" = 10
  dimension "d183" = 10
  constraints: 40 end point, 8 parallel, 5 horizontal, 5 point on line, 4 perpendicular, 1 midpoint, 1 vertical
  measures "d177" distance of L8.end L7.end
  measures "d178" distance of L7.end L6.end
  measures "d179" distance of L11.end L12.end
  measures "d180" distance of L10.end L11.end
  measures "d181" distance of L16.end L15.end
  measures "d182" distance of L15.end L14.end
  measures "d183" distance of L19.end L20.end
extrude "Extrusión19" cut sketch "Boceto18" against normal blind 10 contours L11 L12 L4 L5 | L5 L4 L8 L7 | L19 L20 L3 L2 | L2 L3 L16 L15
sketch "Boceto19" plane through (114.7215, 51.4297, 41) normal (0, 0, -1) x (-1, 0, 0)
  circle A0 centre (69.2395, -145.9987) radius 1.6 projected
  circle A1 centre (69.2395, -172.4987) radius 1.6 projected
  line L0 (69.2395, -145.9987) -> (69.2395, -172.4987)
  line L1 (69.2395, -172.4987) -> (69.2395, -159.2487)
  line L2 (69.2395, -159.2487) -> (0, -159.2487)
  line L3 (0, -149.2487) -> (0, -169.2487) projected
  line L4 (0, -159.2487) -> (210, -159.2487)
  line L5 (210, 0) -> (210, -200) projected
  line L6 (0, -159.2487) -> (10, -159.2487)
  line L7 (10, -159.2487) -> (10, -169.2487)
  line L8 (10, -169.2487) -> (0, -169.2487)
  line L9 (0, -169.2487) -> (0, -159.2487)
  line L10 (0, -159.2487) -> (10, -159.2487)
  line L11 (10, -159.2487) -> (10, -149.2487)
  line L12 (10, -149.2487) -> (0, -149.2487)
  line L13 (0, -149.2487) -> (0, -159.2487)
  line L14 (210, -159.2487) -> (200, -159.2487)
  line L15 (200, -159.2487) -> (200, -169.2487)
  line L16 (200, -169.2487) -> (210, -169.2487)
  line L17 (210, -169.2487) -> (210, -159.2487)
  line L18 (210, -159.2487) -> (200, -159.2487)
  line L19 (200, -159.2487) -> (200, -149.2487)
  line L20 (200, -149.2487) -> (210, -149.2487)
  line L21 (210, -149.2487) -> (210, -159.2487)
  point P0 (114.7215, -51.4297)
  dimension "d186" = 10
  dimension "d187" = 10
  dimension "d188" = 10
  dimension "d189" = 10
  dimension "d190" = 10
  dimension "d191" = 10
  dimension "d192" = 10
  constraints: 40 end point, 8 parallel, 4 horizontal, 4 perpendicular, 3 point on line, 2 midpoint, 1 vertical
  measures "d186" distance of L7.end L8.end
  measures "d187" distance of L6.end L7.end
  measures "d188" distance of L12.end L11.end
  measures "d189" distance of L11.end L10.end
  measures "d190" distance of L16.end L15.end
  measures "d191" distance of L19.end L20.end
  measures "d192" distance of L18.end L19.end
extrude "Extrusión20" cut sketch "Boceto19" against normal blind 10 contours L19 L20 L5 L4 | L4 L5 L16 L15 | L7 L8 L3 L2 | L2 L3 L12 L11
sketch "Boceto20" plane through (73.7215, 51.4297, 210) normal (1, 0, 0) x (0, 0, -1)
  line L0 (3, -47.5) -> (36, -47.5)
  line L1 (36, -47.5) -> (36, -80.5)
  line L2 (36, -80.5) -> (3, -80.5)
  line L3 (3, -80.5) -> (3, -47.5)
  line L4 (41, 0) -> (41, -149.2487) projected
  circle A0 centre (48.5, -64) radius 1.5 projected
  circle A1 centre (6.6, -51.1) radius 1.6
  circle A2 centre (6.6, -77.3) radius 1.6
  circle A3 centre (32.8, -51.1) radius 1.6
  circle A4 centre (32.8, -77.3) radius 1.6
  point P0 (210, -51.4297)
  dimension "d195" = 33
  dimension "d196" = 33
  dimension "d197" = 5
  dimension "d198" = 16.5
  dimension "d199" = 3.2
  dimension "d202" = 26.2
  dimension "d205" = 26.2
  dimension "d208" = 3.2
  dimension "d209" = 3.2
  constraints: 8 end point, 4 centre point, 2 horizontal, 2 parallel, 1 perpendicular, 1 vertical, 6 other
  measures "d195" distance of L1.end L2.end
  measures "d196" distance of L0.end L1.end
  measures "d197" distance between parallel lines of L1 L4
  measures "d198" distance from line of L2 A0.centre
  measures "d199" diameter of A1
  measures "d202" distance of A1.centre A2.centre
  measures "d205" distance of A1.centre A3.centre
  measures "d208" distance from line of L1 A3.centre
  measures "d209" distance from line of L2 A4.centre
sketch "Boceto21" plane through (114.7215, 51.4297, 41) normal (0, 0, -1) x (-1, 0, 0)
  line L0 (3, -47.5) -> (36, -47.5)
  line L1 (36, -47.5) -> (36, -80.5)
  line L2 (36, -80.5) -> (3, -80.5)
  line L3 (3, -80.5) -> (3, -47.5)
  circle A0 centre (48.5, -64) radius 1.5 projected
  line L4 (41, -149.25) -> (41, 0) projected
  circle A1 centre (6.6, -51.1) radius 1.6
  circle A2 centre (6.6, -77.3) radius 1.6
  circle A3 centre (32.8, -51.1) radius 1.6
  circle A4 centre (32.8, -77.3) radius 1.6
  point P0 (114.7215, -51.4297)
  dimension "d210" = 33
  dimension "d211" = 33
  dimension "d212" = 16.5
  dimension "d213" = 5
  dimension "d214" = 3.2
  dimension "d217" = 26.2
  dimension "d220" = 26.2
  dimension "d223" = 3.2
  dimension "d224" = 3.2
  constraints: 8 end point, 4 centre point, 2 horizontal, 2 parallel, 1 perpendicular, 1 vertical, 6 other
  measures "d210" distance of L1.end L2.end
  measures "d211" distance of L0.end L1.end
  measures "d212" distance from line of L2 A0.centre
  measures "d213" distance between parallel lines of L4 L1
  measures "d214" diameter of A1
  measures "d217" distance of A1.centre A2.centre
  measures "d220" distance of A1.centre A3.centre
  measures "d223" distance from line of L2 A4.centre
  measures "d224" distance from line of L1 A4.centre
sketch "Boceto22" plane through (-54.2785, -148.5703, 41) normal (-1, 0, 0) x (0, 0, 1)
  line L0 (-38, 152.5) -> (-5, 152.5)
  line L1 (-5, 152.5) -> (-5, 119.5)
  line L2 (-5, 119.5) -> (-38, 119.5)
  line L3 (-38, 119.5) -> (-38, 152.5)
  circle A0 centre (7.5, 136) radius 1.5 projected
  line L4 (0, 200) -> (0, 50.7513) projected
  circle A1 centre (-34.8, 149.3) radius 1.6
  circle A2 centre (-8.6, 149.3) radius 1.6
  circle A3 centre (-34.8, 123.1) radius 1.6
  circle A4 centre (-8.6, 123.1) radius 1.6
  point P0 (-41, 148.5703)
  dimension "d225" = 33
  dimension "d226" = 33
  dimension "d227" = 16.5
  dimension "d228" = 5
  dimension "d229" = 3.2
  dimension "d230" = 3.2
  dimension "d231" = 3.2
  dimension "d234" = 26.2
  dimension "d237" = 26.2
  constraints: 8 end point, 4 centre point, 2 horizontal, 2 parallel, 1 perpendicular, 1 vertical, 6 other
  measures "d225" distance of L1.end L2.end
  measures "d226" distance of L0.end L1.end
  measures "d227" distance from line of A0.centre L2
  measures "d228" distance between parallel lines of L1 L4
  measures "d229" diameter of A1
  measures "d230" distance from line of L0 A1.centre
  measures "d231" distance from line of L3 A1.centre
  measures "d234" distance of A1.centre A2.centre
  measures "d237" distance of A1.centre A3.centre
sketch "Boceto23" plane through (-95.2785, 51.4297, 169) normal (0, 0, 1) x (1, 0, 0)
  line L0 (3, -47.5) -> (36, -47.5)
  line L1 (36, -47.5) -> (36, -80.5)
  line L2 (36, -80.5) -> (3, -80.5)
  line L3 (3, -80.5) -> (3, -47.5)
  circle A0 centre (48.5, -64) radius 1.5 projected
  line L4 (41, 0) -> (41, -149.25) projected
  circle A1 centre (6.2, -50.7) radius 1.6
  circle A2 centre (32.4, -50.7) radius 1.6
  circle A3 centre (6.2, -76.9) radius 1.6
  circle A4 centre (32.4, -76.9) radius 1.6
  point P0 (95.2785, -51.4297)
  dimension "d240" = 33
  dimension "d241" = 33
  dimension "d242" = 16.5
  dimension "d243" = 5
  dimension "d244" = 3.2
  dimension "d245" = 3.2
  dimension "d246" = 3.2
  dimension "d249" = 26.2
  dimension "d252" = 26.2
  constraints: 8 end point, 4 centre point, 2 horizontal, 2 parallel, 1 perpendicular, 1 vertical, 6 other
  measures "d240" distance of L1.end L2.end
  measures "d241" distance of L0.end L1.end
  measures "d242" distance from line of A0.centre L2
  measures "d243" distance between parallel lines of L1 L4
  measures "d244" diameter of A1
  measures "d245" distance from line of L0 A1.centre
  measures "d246" distance from line of L3 A1.centre
  measures "d249" distance of A1.centre A2.centre
  measures "d252" distance of A1.centre A3.centre
extrude "Extrusión21" cut sketch "Boceto23" against normal blind 10 contours A1 | A2 | A3 | A4
extrude "Extrusión22" cut sketch "Boceto20" against normal blind 10 contours A1 | A2 | A3 | A4
extrude "Extrusión23" cut sketch "Boceto21" against normal blind 10 contours A1 | A2 | A3 | A4
extrude "Extrusión24" cut sketch "Boceto22" against normal blind 10 contours A1 | A2 | A3 | A4
equation "\"d12\" = d8"
equation "\"d13\" = d8"
equation "\"d14\" = 2 * d12"
equation "\"d15\" = d14"
equation "\"d16\" = d14"
equation "\"d17\" = d14"
equation "\"d18\" = d15"
equation "\"d19\" = d18"
equation "\"d20\" = d15"
equation "\"d21\" = d15"
equation "\"d90\" = 0.5 * d89"
